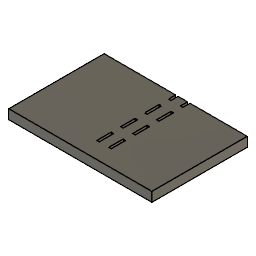
sym_q4_dir2only (Autodesk Fusion 360 design; units mm, degrees)
Autodesk Fusion 360 part; units mm, degrees
sketch "Sketch1" plane through (0, 0, 0) normal (0, 0, 1) x (1, 0, 0)
  line L0 (-30, -20) -> (30, -20)
  line L1 (30, -20) -> (30, 20)
  line L2 (30, 20) -> (-30, 20)
  line L3 (-30, 20) -> (-30, -20)
extrude "Extrude1" add sketch "Sketch1" along normal blind 4
sketch "Sketch2" plane through (0, 0, 4) normal (0, 0, 1) x (1, 0, 0)
  line L0 (-30, 20) -> (-30, -20)
  line L1 (-30, -20) -> (30, -20)
  line L2 (30, -20) -> (30, 20)
  line L3 (30, 20) -> (-30, 20)
  line L4 (0, -3) -> (1, -3)
  line L5 (1, -3) -> (1, 3)
  line L6 (1, 3) -> (0, 3)
  line L7 (0, 3) -> (0, -3)
extrude "Extrude2" cut sketch "Sketch2" against normal blind 1 contours L4 L5 L6 L7
pattern_linear "R-Pattern1" count 2 spacing 5 along (1, 0, 0) count 4 spacing 10 along (0, 1, 0) both ways of "Extrude2"
